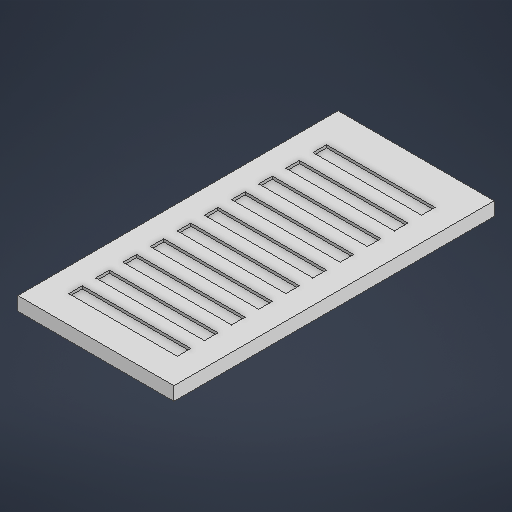
# Autodesk Inventor part: klapka_do_oczu
Saved by Autodesk Inventor 2026.1 (Build 301233020, 233B)
## iProperties
Created: 2026-07-31
Part Number: klapka_do_oczu
Material: Ogólny
Document SubType Name: Modeling
Designer: Nitro
Density: 1 g/cm^3
Appearance: Domyślna
Author: Nitro
Autodesk Inventor part; units mm, degrees
ref_plane "YZ Plane" through (0, 0, 0) normal (1, 0, 0) x (0, 1, 0)
ref_plane "XZ Plane" through (0, 0, 0) normal (0, 1, 0) x (-1, 0, 0)
ref_plane "XY Plane" through (0, 0, 0) normal (0, 0, 1) x (1, 0, 0)
sketch "Szkic1" plane through (0, 0, 0) normal (0, 1, 0) x (-1, 0, 0)
  line L0 (0, 0) -> (23, 0)
  line L1 (23, 0) -> (23, -47.2)
  line L2 (23, -47.2) -> (0, -47.2)
  line L3 (0, -47.2) -> (0, 0)
  dimension "d0" = 23
  dimension "d1" = 47.2
  constraints: 8 end point, 2 parallel, 1 horizontal, 1 perpendicular
  measures "d0" distance of L1.end L2.end
  measures "d1" distance of L0.end L1.end
extrude "Wyciągnięcie proste1" add sketch "Szkic1" along normal blind 2
sketch "Szkic2" plane through (0, 2, 0) normal (0, 1, 0) x (1, 0, 0)
  line L0 (-19.5, 4) -> (-3.5, 4)
  line L1 (-3.5, 4) -> (-3.5, 6)
  line L2 (-3.5, 6) -> (-19.5, 6)
  line L3 (-19.5, 6) -> (-19.5, 4)
  line L4 (-23, 47.2) -> (-23, 0) projected
  line L5 (-23, 0) -> (0, 0) projected
  line L6 (-3.5, 10) -> (-19.5, 10)
  line L7 (-19.5, 8) -> (-3.5, 8)
  line L8 (-19.5, 10) -> (-19.5, 8)
  line L9 (-3.5, 8) -> (-3.5, 10)
  line L10 (-3.5, 14) -> (-19.5, 14)
  line L11 (-19.5, 12) -> (-3.5, 12)
  line L12 (-19.5, 14) -> (-19.5, 12)
  line L13 (-3.5, 12) -> (-3.5, 14)
  line L14 (-3.5, 18) -> (-19.5, 18)
  line L15 (-19.5, 16) -> (-3.5, 16)
  line L16 (-19.5, 18) -> (-19.5, 16)
  line L17 (-3.5, 16) -> (-3.5, 18)
  line L18 (-3.5, 22) -> (-19.5, 22)
  line L19 (-19.5, 20) -> (-3.5, 20)
  line L20 (-19.5, 22) -> (-19.5, 20)
  line L21 (-3.5, 20) -> (-3.5, 22)
  line L22 (-3.5, 26) -> (-19.5, 26)
  line L23 (-19.5, 24) -> (-3.5, 24)
  line L24 (-19.5, 26) -> (-19.5, 24)
  line L25 (-3.5, 24) -> (-3.5, 26)
  line L26 (-3.5, 30) -> (-19.5, 30)
  line L27 (-19.5, 28) -> (-3.5, 28)
  line L28 (-19.5, 30) -> (-19.5, 28)
  line L29 (-3.5, 28) -> (-3.5, 30)
  line L30 (-3.5, 34) -> (-19.5, 34)
  line L31 (-19.5, 32) -> (-3.5, 32)
  line L32 (-19.5, 34) -> (-19.5, 32)
  line L33 (-3.5, 32) -> (-3.5, 34)
  line L34 (-3.5, 38) -> (-19.5, 38)
  line L35 (-19.5, 36) -> (-3.5, 36)
  line L36 (-19.5, 38) -> (-19.5, 36)
  line L37 (-3.5, 36) -> (-3.5, 38)
  line L38 (-3.5, 42) -> (-19.5, 42)
  line L39 (-19.5, 40) -> (-3.5, 40)
  line L40 (-19.5, 42) -> (-19.5, 40)
  line L41 (-3.5, 40) -> (-3.5, 42)
  point P0 (-3.5, 5)
  point P1 (-3.5, 9)
  point P2 (-3.5, 13)
  point P3 (-3.5, 17)
  point P4 (-3.5, 21)
  point P5 (-3.5, 25)
  point P6 (-3.5, 29)
  point P7 (-3.5, 33)
  point P8 (-3.5, 37)
  point P9 (-3.5, 41)
  dimension "d4" = 2
  dimension "d5" = 16
  dimension "d6" = 3.5
  dimension "d7" = 4
  dimension "d10" = 4
  constraints: 80 end point, 2 parallel, 1 collinear, 1 horizontal, 1 midpoint, 1 perpendicular, 1 vertical, 80 other
  measures "d4" distance between parallel lines of L2 L0
  measures "d5" distance from line of point (-3.5, 5) L3
  measures "d6" distance between parallel lines of L4 L3
  measures "d7" distance between parallel lines of L5 L0
  measures "d10" distance of L1.end L6.start
extrude "Wyciągnięcie proste2" cut sketch "Szkic2" against normal blind 0.4
